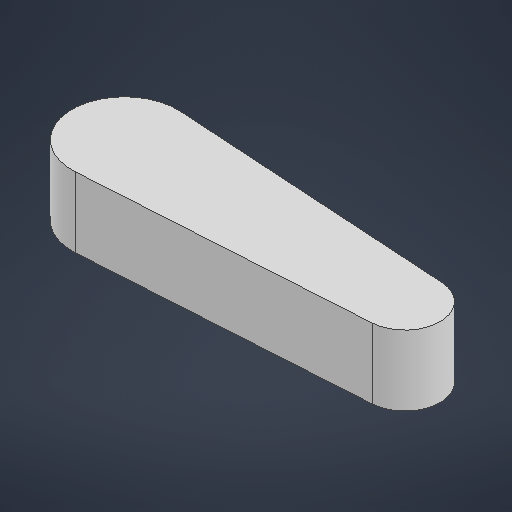
# Autodesk Inventor part: Flipper
Saved by Autodesk Inventor 2027 (Build 310192060, 192F)
## iProperties
Created: 2026-10-17
Part Number: Flipper
Material: Générique
Document SubType Name: Modeling
Designer: strei
Density: 1 g/cm^3
Appearance: Par défaut
Author: strei
Autodesk Inventor part; units mm, degrees
ref_plane "YZ Plane" through (0, 0, 0) normal (1, 0, 0) x (0, 1, 0)
ref_plane "XZ Plane" through (0, 0, 0) normal (0, 1, 0) x (-1, 0, 0)
ref_plane "XY Plane" through (0, 0, 0) normal (0, 0, 1) x (1, 0, 0)
sketch "Esquisse1" plane through (0, 0, 0) normal (0, 1, 0) x (-1, 0, 0)
  circle A0 centre (0, 0) radius 15
  circle A1 centre (-80, 0) radius 10
  line L0 (-0.9375, -14.9707) -> (-80.625, -9.9804)
  line L1 (-0.9375, 14.9707) -> (-80.625, 9.9804)
  dimension "d0" = 30
  dimension "d1" = 20
  dimension "d2" = 80
  constraints: 4 end point, 4 point on circle, 4 tangent, 2 centre point, 1 coincident, 1 horizontal alignment
  measures "d0" diameter of A0
  measures "d1" diameter of A1
  measures "d2" distance of A1.centre point (0, 0)
extrude "Extrusion1" add sketch "Esquisse1" along normal blind 20
sketch "Esquisse2" plane through (0, 0, 0) normal (0, -1, 0) x (1, 0, 0)
  point P0 (0, 0)
  point P1 (0, 0)
  constraints: 1 coincident
hole "Perçage1" at (0, 0, 0) direction (0, 1, 0) diameter 5 depth 10
